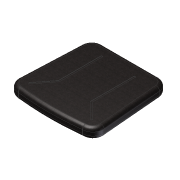
# Autodesk Inventor part: Sediste
Saved by Autodesk Inventor 2012 (Build 160160000, 160)
## iProperties
Created: 2009-08-13
Part Number: Sediste
Document SubType Name: Modeling
Designer: Milos Zaric
Density: 1 g/cm^3
Material: Default
Author: Milos Zaric
Autodesk Inventor part; units mm, degrees
ref_plane "YZ Plane" through (0, 0, 0) normal (1, 0, 0) x (0, 1, 0)
ref_plane "XZ Plane" through (0, 0, 0) normal (0, 1, 0) x (-1, 0, 0)
ref_plane "XY Plane" through (0, 0, 0) normal (0, 0, 1) x (1, 0, 0)
sketch "Sketch1" plane through (0, 0, 0) normal (0, 0, 1) x (1, 0, 0)
  line L0 (50.3326, 26.0718) -> (377.721, 26.0718)
  line L1 (407.5082, -443.9282) -> (35.439, -443.9282)
  line L2 (-9.6131, -31.3773) -> (-24.5068, -381.3773)
  line L3 (467.2921, -378.8402) -> (437.5049, -28.8402)
  arc A0 (-24.5068, -381.3773) -> (35.439, -443.9282) centre (35.439, -383.9282) ccw
  arc A1 (407.5082, -443.9282) -> (467.2921, -378.8402) centre (407.5082, -383.9282) ccw
  arc A2 (35.439, -443.9282) -> (407.5082, -443.9282) centre (221.4736, 1207.0555) ccw
  arc A3 (50.3326, 26.0718) -> (-9.6131, -31.3773) centre (50.3326, -33.9282) ccw
  arc A4 (437.5049, -28.8402) -> (377.721, 26.0718) centre (377.721, -33.9282) ccw
  point P0 (-27.1685, 26.0718)
  point P1 (452.8315, 26.0718)
  point P2 (-27.1685, -443.9282)
  point P3 (-7.1685, 26.0718)
  point P4 (432.8315, 26.0718)
  dimension "d0" = 480
  dimension "d1" = 470
  dimension "d2" = 20
  dimension "d3" = 20
  dimension "d4" = 60
  dimension "d5" = 60
  constraints: 10 point on circle, 8 end point, 8 point on line, 8 tangent, 5 centre point, 2 equal radius, 1 horizontal, 1 parallel
  measures "d0" distance of point (-27.168, 26.072) point (452.832, 26.072)
  measures "d1" distance of point (-27.168, -443.928) point (-27.168, 26.072)
  measures "d2" distance of point (-7.168, 26.072) point (-27.168, 26.072)
  measures "d3" distance of point (452.832, 26.072) point (432.832, 26.072)
  measures "d4" radius of A0
  measures "d5" radius of A3
extrude "Extrusion1" add sketch "Sketch1" along normal blind 60
fillet "Fillet1" radius 20 18 edges at (-7.8799, -425.443, 60) (-7.8799, -425.443, 0) (35.439, -443.9282, 30) (-17.0599, -206.3773, 60) (-17.0599, -206.3773, 0) (8.8179, 9.3907, 60) (8.8179, 9.3907, 0) (214.0268, 26.0718, 60) (214.0268, 26.0718, 0) (418.3087, 10.2605, 60) (418.3087, 10.2605, 0) (452.3985, -203.8402, 60) (452.3985, -203.8402, 0) (451.6969, -424.5159, 60) (407.5082, -443.9282, 30) (451.6969, -424.5159, 0) (221.4736, -454.3764, 60) (221.4736, -454.3764, 0)
sketch "Sketch3" plane through (0, 0, 0) normal (0, 0, -1) x (-1, 0, 0)
  line L0 (-377.721, 6.0718) -> (-50.3326, 6.0718) projected
  arc A0 (-404.2543, -424.168) -> (-38.6929, -424.168) centre (-221.4736, 1207.0555) ccw projected
  line L1 (-214.0268, 6.0718) -> (-214.0268, -434.3596)
  line L2 (-214.0268, -214.1439) -> (-248.6384, -214.1439)
  constraints: 4 end point, 2 midpoint, 2 perpendicular, 1 coincident, 1 point on circle
hole "Hole1" at (214.0268, -214.1439, 0) direction (0, 0, 1) diameter 20 depth 8 tip angle 118
sketch "Sketch4" plane through (0, 0, 60) normal (0, 0, 1) x (1, 0, 0)
  arc A0 (408.1084, -423.9237) -> (447.3641, -380.5362) centre (407.5082, -383.9282) ccw projected
  arc A1 (417.5769, -30.5362) -> (377.721, 6.0718) centre (377.721, -33.9282) ccw projected
  line L0 (50.3326, 6.0718) -> (377.721, 6.0718) projected
  arc A2 (50.3326, 6.0718) -> (10.3688, -32.2276) centre (50.3326, -33.9282) ccw projected
  arc A3 (-4.5248, -382.2276) -> (34.8389, -423.9237) centre (35.439, -383.9282) ccw projected
  line L1 (35.439, -383.9282) -> (110.3326, -287.263)
  line L2 (110.3326, -287.263) -> (110.3326, -37.263)
  line L3 (317.721, -46.0044) -> (317.721, -296.0044)
  line L4 (317.721, -296.0044) -> (407.5082, -383.9282)
  line L5 (120.3326, -38.1413) -> (120.3326, -290.6836)
  line L6 (120.3326, -290.6836) -> (43.344, -390.0528)
  line L7 (307.721, -45.1262) -> (307.721, -300.2081)
  line L8 (307.721, -300.2081) -> (401.3475, -391.8915)
  line L9 (35.439, -383.9282) -> (43.344, -390.0528)
  line L10 (401.3475, -391.8915) -> (407.5172, -383.9282)
  line L11 (307.721, -45.1262) -> (317.721, -46.0044)
  line L12 (110.3326, -37.263) -> (120.3326, -38.1413)
  line L13 (307.721, -45.1262) -> (317.721, -46.0044)
  line L14 (401.3475, -391.8915) -> (407.5172, -383.9282)
  line L15 (407.5133, -383.9332) -> (317.721, -296.0044)
  line L16 (307.721, -300.2081) -> (401.3475, -391.8915)
  line L17 (307.721, -300.2081) -> (307.721, -45.1262)
  line L18 (317.721, -46.0044) -> (317.721, -296.0044)
  dimension "d19" = 60
  dimension "d20" = 60
  dimension "d21" = 250
  dimension "d22" = 250
  dimension "d23" = 252.5424
  dimension "d24" = 10
  dimension "d25" = 10
  constraints: 36 end point, 4 collinear, 3 parallel, 3 perpendicular, 2 point on line, 2 other
  measures "d19" horizontal distance of L2.end A2.centre
  measures "d20" distance from line of A1.centre L3
  measures "d21" distance of L1.end L2.end
  measures "d22" distance of L3.start L3.end
  measures "d23" distance of L5.start L5.end
  measures "d24" distance between parallel lines of L5 L2
  measures "d25" distance between parallel lines of L7 L3
extrude "Extrusion2" cut sketch "Sketch4" against normal blind 2
body "Solid1"
